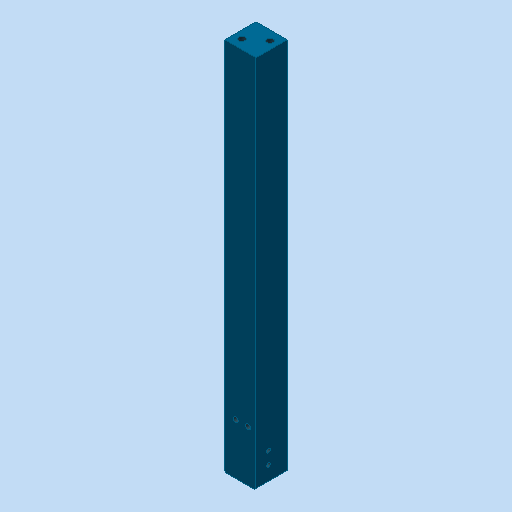
# Autodesk Inventor part: MM0937AN100_G01_126
Saved by Autodesk Inventor 2023.3 (Build 273359000, 359)
## iProperties
RuleStatus: InUse
Created: 2020-12-08
Part Number: MM0937AN100_G01_126
Material: 3.3547 AlMg4,5Mn0,7 - AW 5083
Description: =<RBPARTNOTITLE2>
Document SubType Name: Modeling
Designer: RUD
Mass: 257.029 g
Surface Area: 208.507 cm^2
Volume: 95.196 cm^3
Density: 2.7 g/cm^3
Appearance: Cyan-D
AnP_Kategorie: 1
AnP_Material: =<Material>
MaxAbmaße: 20 x 240 x 20 (FM)
AnP_TemplVers: 20200821
RBDOCUMENTTYPE: DRF
RBDOCUMENTVERSION: 00
RBDRAWINGMAINSCALE: 1:1
RBDRAWINGMISSINGSPEC: --
RBDRAWINGVOLUME: --
RBDSV1: 0850
RBGBEDGESIN1: +0,5
RBGBEDGESIN2: +0,2
RBGBEDGESOUT1: -0,3
RBGBEDGESOUT2: -0,1
RBMATERIAL: =<Material>
RBMATMEETS: --
RBMATNO: =<Part Number>
RBPARTMADEOF: 20 x 240 x 20 (FM)
RBPARTNO: SIEHE MNR
RBPARTNOTITLE1: manufactured part
RBPARTNOTITLE2: Anfertigungsteil
RBPARTSAFETYINDICATOR: --
RBSURFACE: anodised colourless
RBSURFACE2: eloxiert farblos
RBZEDGESNORM: ISO13715:2002-06
RBZGENDIMCLASS: m
RBZGENDIMNORM: ISO 2768-1:1989-11
RBZGENGEOCLASS: H
RBZGENGEONORM: ISO 2768-2:1989-11
RBZSURFACENORM: ISO13D2:2002-02
RBZTOLERANCENORM: ISO 14405-1:2010-12
Author: RUD
Keywords: =<RBPARTMADEOF>
Comments: =<RBSURFACE2>
Revision Number: 01
Autodesk Inventor part; units mm, degrees
ref_plane "YZ Plane" through (0, 0, 0) normal (1, 0, 0) x (0, 1, 0)
ref_plane "XZ Plane" through (0, 0, 0) normal (0, 1, 0) x (-1, 0, 0)
ref_plane "XY Plane" through (0, 0, 0) normal (0, 0, 1) x (1, 0, 0)
sketch "Skizze1" plane through (0, 0, 0) normal (0, 0, 1) x (1, 0, 0)
  line L0 (0, 48) -> (0, -288) projected
  line L1 (-14, 0) -> (14, 0) projected
  line L2 (10, 0) -> (-10, 0)
  line L3 (-10, 0) -> (-10, -240)
  line L4 (-10, -240) -> (10, -240)
  line L5 (10, -240) -> (10, 0)
  dimension "d0" = 20
  dimension "d1" = 240
  constraints: 8 end point, 2 parallel, 1 horizontal, 1 perpendicular, 1 point on line, 1 other
  measures "d0" distance between parallel lines of L5 L3
  measures "d1" distance between parallel lines of L4 L1
extrude "Extrusion1" add sketch "Skizze1" along normal mid plane 20
sketch "Skizze2" plane through (-10, 0, 10) normal (0, 1, 0) x (1, 0, 0)
  line L0 (10, 24) -> (10, -4) projected
  line L1 (24, 10) -> (-4, 10) projected
  line L2 (15, 14) -> (5, 6)
  point P0 (10, 10)
  dimension "d4" = 10
  dimension "d5" = 8
  constraints: 3 midpoint, 2 coincident, 2 end point
  measures "d4" horizontal distance of point (15, 14) point (5, 6)
  measures "d5" vertical distance of point (5, 6) point (15, 14)
hole "Bohrung1" at (5, 0, -4) at (-5, 0, 4) direction (0, -1, 0) diameter 4.134 depth 17 tip angle 118 thread size "M5x0.8" designation "M5" class "6H" standard "ISO Metric profile"
sketch "Skizze3" plane through (0, 0, 10) normal (0, 0, 1) x (1, 0, 0)
  line L0 (-10, -240) -> (10, -240) projected
  line L1 (-3, -207.3) -> (5, -207.3)
  line L2 (10, -240) -> (10, 0) projected
  dimension "d13" = 32.7
  dimension "d15" = 8
  dimension "d23" = 5
  constraints: 2 coincident, 2 end point, 1 horizontal
  measures "d13" distance from line of L0 point (-3, -207.3)
  measures "d15" distance of point (-3, -207.3) point (5, -207.3)
  measures "d23" distance from line of point (5, -207.3) L2
hole "Bohrung2" at (-3, -207.3, 10) at (5, -207.3, 10) direction (0, 0, -1) diameter 3.242 depth 11.8 tip angle 118 thread size "M4x0.7" designation "M4" class "6H" standard "ISO Metric profile"
sketch "Skizze4" plane through (10, -240, 10) normal (1, 0, 0) x (0, 0, -1)
  line L0 (20, 0) -> (0, 0) projected
  line L1 (20, 240) -> (20, 0) projected
  line L2 (8, 10) -> (8, 18)
  dimension "d24" = 12
  dimension "d25" = 8
  dimension "d26" = 10
  constraints: 2 coincident, 2 end point, 1 vertical
  measures "d24" distance from line of L1 point (8, 10)
  measures "d25" distance of L2.start L2.end
  measures "d26" distance from line of L0 point (8, 10)
hole "Bohrung3" at (10, -230, 2) at (10, -222, 2) direction (-1, 0, 0) diameter 2.459 depth 12 tip angle 118 thread size "M3x0.5" designation "M3" class "6H" standard "ISO Metric profile"
chamfer "Fase1" distance 1 angle 45 2 edges at (10, -240, 0) (-10, -240, 0)
